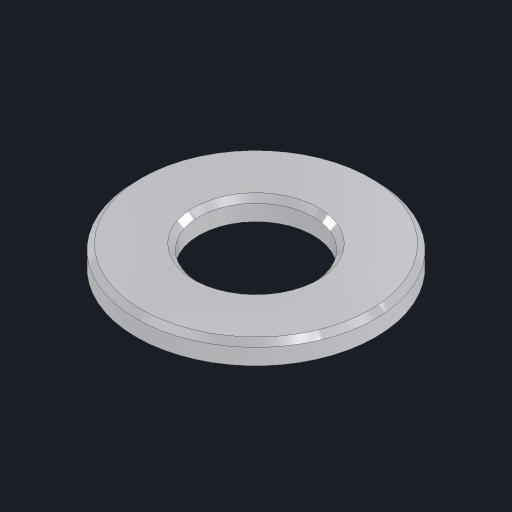
# Autodesk Inventor part: Arruela Lisa DIN 125 - B4 - 300 HV
Saved by Autodesk Inventor 2024.3 (Build 283343000, 343)
## iProperties
Created: 2025-02-01
Part Number: Arruela Lisa DIN 125 - B4 - 300 HV
Material: Aço, carbono
Document SubType Name: Modeling
Designer: Cliente
Density: 7.85 g/cm^3
Appearance: Aço suave - Soldado
Mass: 0.301758 g
Surface Area: 1.26722 cm^2
Volume: 0.0384405 cm^3
Author: Cliente
Autodesk Inventor part; units mm, degrees
ref_plane "YZ Plane" through (0, 0, 0) normal (1, 0, 0) x (0, 1, 0)
ref_plane "XZ Plane" through (0, 0, 0) normal (0, 1, 0) x (-1, 0, 0)
ref_plane "XY Plane" through (0, 0, 0) normal (0, 0, 1) x (1, 0, 0)
sketch "Esboço1" plane through (0, 0, 0) normal (0, 1, 0) x (-1, 0, 0)
  circle A0 centre (0, 0) radius 4.5
  circle A1 centre (0, 0) radius 2.15
  dimension "d0" = 9
  dimension "d1" = 4.3
  constraints: 2 centre point, 2 coincident
  measures "d0" diameter of A0
  measures "d1" diameter of A1
extrude "Extrusão1" add sketch "Esboço1" along normal mid plane 0.8
chamfer "Chanfro1" distance 0.2 angle 45 1 edges at (4.5, 0.4, 0)
sketch "Esboço2" plane through (0, 0, 0) normal (0, 0, 1) x (1, 0, 0)
  line L0 (-2.15, 0.4) -> (-2.15, -0.4) projected
  line L1 (-2.15, 0.4) -> (2.15, 0.4) projected
  line L2 (-4.3, 0.4) -> (4.3, 0.4) projected
  line L3 (0, 0.4) -> (-2.35, 0.4)
  line L4 (-2.35, 0.4) -> (-2.15, 0.2)
  line L5 (0, -0.56) -> (0, 0.56) projected
  point P0 (0, 0)
  dimension "d7" = 2.35
  dimension "d8" = 45
  constraints: 4 end point, 2 point on line, 1 midpoint
  measures "d7" distance of L3.start L3.end
  measures "d8" angle of L4 L2
revolve "Revolução1" cut sketch "Esboço2" angle 360 about axis through (0, -10, 0) along (0, 1, 0)
